Autodesk Fusion 360 part; units mm, degrees
(part 2 of 2)
sketch "スケッチ14" plane through (0, 0, 4.3) normal (0, 0, 1) x (1, 0, 0) in component "Upper_L_PROTECTIVE_ROOF_23_LP_OPENINGS_PROVISIONAL"
  line L0 (-31.4193, -16.4062) -> (-45.5193, -16.4062)
  line L1 (-45.5193, -16.4062) -> (-45.5193, -30.5062)
  line L2 (-45.5193, -30.5062) -> (-31.4193, -30.5062)
  line L3 (-31.4193, -30.5062) -> (-31.4193, -16.4062)
  line L4 (-12.3693, -18.9065) -> (-26.4693, -18.9065)
  line L5 (-26.4693, -18.9065) -> (-26.4693, -33.0065)
  line L6 (-26.4693, -33.0065) -> (-12.3693, -33.0065)
  line L7 (-12.3693, -33.0065) -> (-12.3693, -18.9065)
  line L8 (-50.4937, -51.986) -> (-64.5937, -51.986)
  line L9 (-64.5937, -51.986) -> (-64.5937, -66.086)
  line L10 (-64.5937, -66.086) -> (-50.4937, -66.086)
  line L11 (-50.4937, -66.086) -> (-50.4937, -51.986)
  line L12 (-1.074, -80.3405) -> (12.1756, -85.163)
  line L13 (12.1756, -85.163) -> (16.9981, -71.9133)
  line L14 (16.9981, -71.9133) -> (3.7485, -67.0908)
  line L15 (3.7485, -67.0908) -> (-1.074, -80.3405)
  line L16 (-12.3693, -37.9565) -> (-26.4693, -37.9565)
  line L17 (-26.4693, -37.9565) -> (-26.4693, -52.0565)
  line L18 (-26.4693, -52.0565) -> (-12.3693, -52.0565)
  line L19 (-12.3693, -52.0565) -> (-12.3693, -37.9565)
  line L20 (-88.5693, -6.556) -> (-102.6693, -6.556)
  line L21 (-102.6693, -6.556) -> (-102.6693, -20.656)
  line L22 (-102.6693, -20.656) -> (-88.5693, -20.656)
  line L23 (-88.5693, -20.656) -> (-88.5693, -6.556)
  line L24 (-31.4193, 2.6438) -> (-45.5193, 2.6438)
  line L25 (-45.5193, 2.6438) -> (-45.5193, -11.4562)
  line L26 (-45.5193, -11.4562) -> (-31.4193, -11.4562)
  line L27 (-31.4193, -11.4562) -> (-31.4193, 2.6438)
  line L28 (-50.4693, -13.906) -> (-64.5693, -13.906)
  line L29 (-64.5693, -13.906) -> (-64.5693, -28.006)
  line L30 (-64.5693, -28.006) -> (-50.4693, -28.006)
  line L31 (-50.4693, -28.006) -> (-50.4693, -13.906)
  line L32 (-50.4693, 5.144) -> (-64.5693, 5.144)
  line L33 (-64.5693, 5.144) -> (-64.5693, -8.956)
  line L34 (-64.5693, -8.956) -> (-50.4693, -8.956)
  line L35 (-50.4693, -8.956) -> (-50.4693, 5.144)
  line L36 (-31.4193, -35.4562) -> (-45.5193, -35.4562)
  line L37 (-45.5193, -35.4562) -> (-45.5193, -49.5562)
  line L38 (-45.5193, -49.5562) -> (-31.4193, -49.5562)
  line L39 (-31.4193, -49.5562) -> (-31.4193, -35.4562)
  line L40 (-50.4693, -32.956) -> (-64.5693, -32.956)
  line L41 (-64.5693, -32.956) -> (-64.5693, -47.056)
  line L42 (-64.5693, -47.056) -> (-50.4693, -47.056)
  line L43 (-50.4693, -47.056) -> (-50.4693, -32.956)
  line L44 (-69.5193, 0.4435) -> (-83.6193, 0.4435)
  line L45 (-83.6193, 0.4435) -> (-83.6193, -13.6565)
  line L46 (-83.6193, -13.6565) -> (-69.5193, -13.6565)
  line L47 (-69.5193, -13.6565) -> (-69.5193, 0.4435)
  line L48 (-88.5693, -63.706) -> (-102.6693, -63.706)
  line L49 (-102.6693, -63.706) -> (-102.6693, -77.806)
  line L50 (-102.6693, -77.806) -> (-88.5693, -77.806)
  line L51 (-88.5693, -77.806) -> (-88.5693, -63.706)
  line L52 (-12.3693, 0.1435) -> (-26.4693, 0.1435)
  line L53 (-26.4693, 0.1435) -> (-26.4693, -13.9565)
  line L54 (-26.4693, -13.9565) -> (-12.3693, -13.9565)
  line L55 (-12.3693, -13.9565) -> (-12.3693, 0.1435)
  line L56 (6.6807, -42.481) -> (-7.4193, -42.481)
  line L57 (-7.4193, -42.481) -> (-7.4193, -56.581)
  line L58 (-7.4193, -56.581) -> (6.6807, -56.581)
  line L59 (6.6807, -56.581) -> (6.6807, -42.481)
  line L60 (-69.5193, -18.6065) -> (-83.6193, -18.6065)
  line L61 (-83.6193, -18.6065) -> (-83.6193, -32.7065)
  line L62 (-83.6193, -32.7065) -> (-69.5193, -32.7065)
  line L63 (-69.5193, -32.7065) -> (-69.5193, -18.6065)
  line L64 (6.6907, -23.436) -> (-7.4093, -23.436)
  line L65 (-7.4093, -23.436) -> (-7.4093, -37.536)
  line L66 (-7.4093, -37.536) -> (6.6907, -37.536)
  line L67 (6.6907, -37.536) -> (6.6907, -23.436)
  line L68 (-88.5693, -44.656) -> (-102.6693, -44.656)
  line L69 (-102.6693, -44.656) -> (-102.6693, -58.756)
  line L70 (-102.6693, -58.756) -> (-88.5693, -58.756)
  line L71 (-88.5693, -58.756) -> (-88.5693, -44.656)
  line L72 (-88.5693, -25.606) -> (-102.6693, -25.606)
  line L73 (-102.6693, -25.606) -> (-102.6693, -39.706)
  line L74 (-102.6693, -39.706) -> (-88.5693, -39.706)
  line L75 (-88.5693, -39.706) -> (-88.5693, -25.606)
  line L76 (-41.5023, -75.8813) -> (-27.4023, -75.8813)
  line L77 (-27.4023, -75.8813) -> (-27.4023, -61.7813)
  line L78 (-27.4023, -61.7813) -> (-41.5023, -61.7813)
  line L79 (-41.5023, -61.7813) -> (-41.5023, -75.8813)
  line L80 (-69.5193, -56.7065) -> (-83.6193, -56.7065)
  line L81 (-83.6193, -56.7065) -> (-83.6193, -70.8065)
  line L82 (-83.6193, -70.8065) -> (-69.5193, -70.8065)
  line L83 (-69.5193, -70.8065) -> (-69.5193, -56.7065)
  line L84 (-69.5193, -37.6565) -> (-83.6193, -37.6565)
  line L85 (-83.6193, -37.6565) -> (-83.6193, -51.7565)
  line L86 (-83.6193, -51.7565) -> (-69.5193, -51.7565)
  line L87 (-69.5193, -51.7565) -> (-69.5193, -37.6565)
  line L88 (-21.1812, -76.4316) -> (-7.2547, -78.6373)
  line L89 (-7.2547, -78.6373) -> (-5.049, -64.7109)
  line L90 (-5.049, -64.7109) -> (-18.9754, -62.5052)
  line L91 (-18.9754, -62.5052) -> (-21.1812, -76.4316)
extrude "Twenty_three_LP_openings_14p1" cut sketch "スケッチ14" along normal blind 1.2 bodies 6 in component "Upper_L_PROTECTIVE_ROOF_23_LP_OPENINGS_PROVISIONAL"
sketch "スケッチ15" plane through (0, 0, 4.3) normal (0, 0, 1) x (1, 0, 0) in component "Upper_L_PROTECTIVE_ROOF_23_LP_OPENINGS_PROVISIONAL"
  circle A0 centre (-31.7729, -16.7598) radius 0.5
  circle A1 centre (-31.7729, -30.1527) radius 0.5
  circle A2 centre (-45.1658, -16.7598) radius 0.5
  circle A3 centre (-45.1658, -30.1527) radius 0.5
  circle A4 centre (-12.7229, -19.2601) radius 0.5
  circle A5 centre (-12.7229, -32.6529) radius 0.5
  circle A6 centre (-26.1158, -19.2601) radius 0.5
  circle A7 centre (-26.1158, -32.6529) radius 0.5
  circle A8 centre (-50.8472, -52.3396) radius 0.5
  circle A9 centre (-50.8472, -65.7324) radius 0.5
  circle A10 centre (-64.2401, -52.3396) radius 0.5
  circle A11 centre (-64.2401, -65.7324) radius 0.5
  circle A12 centre (-0.6209, -80.1292) radius 0.5
  circle A13 centre (3.9598, -67.544) radius 0.5
  circle A14 centre (11.9643, -84.7098) radius 0.5
  circle A15 centre (16.545, -72.1246) radius 0.5
  circle A16 centre (-12.7229, -38.3101) radius 0.5
  circle A17 centre (-12.7229, -51.7029) radius 0.5
  circle A18 centre (-26.1158, -38.3101) radius 0.5
  circle A19 centre (-26.1158, -51.7029) radius 0.5
  circle A20 centre (-88.9229, -6.9096) radius 0.5
  circle A21 centre (-88.9229, -20.3024) radius 0.5
  circle A22 centre (-102.3158, -6.9096) radius 0.5
  circle A23 centre (-102.3158, -20.3024) radius 0.5
  circle A24 centre (-31.7729, 2.2902) radius 0.5
  circle A25 centre (-31.7729, -11.1027) radius 0.5
  circle A26 centre (-45.1658, 2.2902) radius 0.5
  circle A27 centre (-45.1658, -11.1027) radius 0.5
  circle A28 centre (-50.8229, -14.2596) radius 0.5
  circle A29 centre (-50.8229, -27.6524) radius 0.5
  circle A30 centre (-64.2158, -14.2596) radius 0.5
  circle A31 centre (-64.2158, -27.6524) radius 0.5
  circle A32 centre (-50.8229, 4.7904) radius 0.5
  circle A33 centre (-50.8229, -8.6024) radius 0.5
  circle A34 centre (-64.2158, 4.7904) radius 0.5
  circle A35 centre (-64.2158, -8.6024) radius 0.5
  circle A36 centre (-31.7729, -35.8098) radius 0.5
  circle A37 centre (-31.7729, -49.2027) radius 0.5
  circle A38 centre (-45.1658, -35.8098) radius 0.5
  circle A39 centre (-45.1658, -49.2027) radius 0.5
  circle A40 centre (-50.8229, -33.3096) radius 0.5
  circle A41 centre (-50.8229, -46.7024) radius 0.5
  circle A42 centre (-64.2158, -33.3096) radius 0.5
  circle A43 centre (-64.2158, -46.7024) radius 0.5
  circle A44 centre (-69.8729, 0.0899) radius 0.5
  circle A45 centre (-69.8729, -13.3029) radius 0.5
  circle A46 centre (-83.2658, 0.0899) radius 0.5
  circle A47 centre (-83.2658, -13.3029) radius 0.5
  circle A48 centre (-88.9229, -64.0596) radius 0.5
  circle A49 centre (-88.9229, -77.4524) radius 0.5
  circle A50 centre (-102.3158, -64.0596) radius 0.5
  circle A51 centre (-102.3158, -77.4524) radius 0.5
  circle A52 centre (-12.7229, -0.2101) radius 0.5
  circle A53 centre (-12.7229, -13.6029) radius 0.5
  circle A54 centre (-26.1158, -0.2101) radius 0.5
  circle A55 centre (-26.1158, -13.6029) radius 0.5
  circle A56 centre (6.3271, -42.8346) radius 0.5
  circle A57 centre (6.3271, -56.2274) radius 0.5
  circle A58 centre (-7.0658, -42.8346) radius 0.5
  circle A59 centre (-7.0658, -56.2274) radius 0.5
  circle A60 centre (-69.8729, -18.9601) radius 0.5
  circle A61 centre (-69.8729, -32.3529) radius 0.5
  circle A62 centre (-83.2658, -18.9601) radius 0.5
  circle A63 centre (-83.2658, -32.3529) radius 0.5
  circle A64 centre (6.3371, -23.7896) radius 0.5
  circle A65 centre (6.3371, -37.1824) radius 0.5
  circle A66 centre (-7.0558, -23.7896) radius 0.5
  circle A67 centre (-7.0558, -37.1824) radius 0.5
  circle A68 centre (-88.9229, -45.0096) radius 0.5
  circle A69 centre (-88.9229, -58.4024) radius 0.5
  circle A70 centre (-102.3158, -45.0096) radius 0.5
  circle A71 centre (-102.3158, -58.4024) radius 0.5
  circle A72 centre (-88.9229, -25.9596) radius 0.5
  circle A73 centre (-88.9229, -39.3524) radius 0.5
  circle A74 centre (-102.3158, -25.9596) radius 0.5
  circle A75 centre (-102.3158, -39.3524) radius 0.5
  circle A76 centre (-41.1488, -75.5277) radius 0.5
  circle A77 centre (-41.1488, -62.1348) radius 0.5
  circle A78 centre (-27.7559, -75.5277) radius 0.5
  circle A79 centre (-27.7559, -62.1348) radius 0.5
  circle A80 centre (-69.8729, -57.0601) radius 0.5
  circle A81 centre (-69.8729, -70.4529) radius 0.5
  circle A82 centre (-83.2658, -57.0601) radius 0.5
  circle A83 centre (-83.2658, -70.4529) radius 0.5
  circle A84 centre (-69.8729, -38.0101) radius 0.5
  circle A85 centre (-69.8729, -51.4029) radius 0.5
  circle A86 centre (-83.2658, -38.0101) radius 0.5
  circle A87 centre (-83.2658, -51.4029) radius 0.5
  circle A88 centre (-20.7766, -76.1377) radius 0.5
  circle A89 centre (-18.6815, -62.9097) radius 0.5
  circle A90 centre (-7.5486, -78.2328) radius 0.5
  circle A91 centre (-5.4535, -65.0048) radius 0.5
extrude "Ninety_two_corner_reliefs_R0p5" cut sketch "スケッチ15" along normal blind 1.2 bodies 6 in component "Upper_L_PROTECTIVE_ROOF_23_LP_OPENINGS_PROVISIONAL"
sketch "スケッチ16" plane through (0, 0, 4.3) normal (0, 0, 1) x (1, 0, 0) in component "Upper_L_PROTECTIVE_ROOF_23_LP_OPENINGS_PROVISIONAL"
  line L0 (-9.5, -21.1) -> (9.5, -21.1)
  line L1 (9.5, -21.1) -> (9.5, 2.6)
  line L2 (9.5, 2.6) -> (-9.5, 2.6)
  line L3 (-9.5, 2.6) -> (-9.5, -21.1)
extrude "Controller_opening_for_separate_nonmetal_cover" cut sketch "スケッチ16" along normal blind 1.2 bodies 6 in component "Upper_L_PROTECTIVE_ROOF_23_LP_OPENINGS_PROVISIONAL"
combine "Join_perforated_roof_to_perimeter_only" operation add target body 2 tool bodies 6 in component "Upper_L_PROTECTIVE_ROOF_23_LP_OPENINGS_PROVISIONAL"
ref_plane "作業平面1" through (0, 0, 3) normal (0, 0, 1) x (1, 0, 0) in component "MCU_NONMETAL_COVER_CONCEPT_RETENTION_PENDING"
sketch "スケッチ1 (6)" plane through (0, 0, 3) normal (0, 0, 1) x (1, 0, 0) in component "MCU_NONMETAL_COVER_CONCEPT_RETENTION_PENDING"
  line L0 (-9.9, -20.95) -> (9.9, -20.95)
  line L1 (9.9, -20.95) -> (9.9, 3)
  line L2 (9.9, 3) -> (-9.9, 3)
  line L3 (-9.9, 3) -> (-9.9, -20.95)
extrude "押し出し1''" add sketch "スケッチ1 (6)" along normal blind 1.2 separate body makes body 7 in component "MCU_NONMETAL_COVER_CONCEPT_RETENTION_PENDING"
ref_plane "作業平面2" through (0, 0, 0) normal (0, 0, 1) x (1, 0, 0) in component "MCU_NONMETAL_COVER_CONCEPT_RETENTION_PENDING"
sketch "スケッチ2 (4)" plane through (0, 0, 0) normal (0, 0, 1) x (1, 0, 0) in component "MCU_NONMETAL_COVER_CONCEPT_RETENTION_PENDING"
  line L0 (-9.9, -20.95) -> (-9.1, -20.95)
  line L1 (-9.1, -20.95) -> (-9.1, 3)
  line L2 (-9.1, 3) -> (-9.9, 3)
  line L3 (-9.9, 3) -> (-9.9, -20.95)
extrude "押し出し2" add sketch "スケッチ2 (4)" along normal blind 3 separate body makes body 8 in component "MCU_NONMETAL_COVER_CONCEPT_RETENTION_PENDING"
ref_plane "作業平面3" through (0, 0, 0) normal (0, 0, 1) x (1, 0, 0) in component "MCU_NONMETAL_COVER_CONCEPT_RETENTION_PENDING"
sketch "スケッチ3 (3)" plane through (0, 0, 0) normal (0, 0, 1) x (1, 0, 0) in component "MCU_NONMETAL_COVER_CONCEPT_RETENTION_PENDING"
  line L0 (9.1, -20.95) -> (9.9, -20.95)
  line L1 (9.9, -20.95) -> (9.9, 3)
  line L2 (9.9, 3) -> (9.1, 3)
  line L3 (9.1, 3) -> (9.1, -20.95)
extrude "押し出し3" add sketch "スケッチ3 (3)" along normal blind 3 separate body makes body 9 in component "MCU_NONMETAL_COVER_CONCEPT_RETENTION_PENDING"
ref_plane "作業平面4" through (0, 0, 0) normal (0, 0, 1) x (1, 0, 0) in component "MCU_NONMETAL_COVER_CONCEPT_RETENTION_PENDING"
sketch "スケッチ4 (3)" plane through (0, 0, 0) normal (0, 0, 1) x (1, 0, 0) in component "MCU_NONMETAL_COVER_CONCEPT_RETENTION_PENDING"
  line L0 (-9.9, 2.2) -> (9.9, 2.2)
  line L1 (9.9, 2.2) -> (9.9, 3)
  line L2 (9.9, 3) -> (-9.9, 3)
  line L3 (-9.9, 3) -> (-9.9, 2.2)
extrude "押し出し4" add sketch "スケッチ4 (3)" along normal blind 3 separate body makes body 10 in component "MCU_NONMETAL_COVER_CONCEPT_RETENTION_PENDING"
ref_plane "作業平面5" through (0, 0, 0.7) normal (0, 0, 1) x (1, 0, 0) in component "MCU_NONMETAL_COVER_CONCEPT_RETENTION_PENDING"
sketch "スケッチ5 (3)" plane through (0, 0, 0.7) normal (0, 0, 1) x (1, 0, 0) in component "MCU_NONMETAL_COVER_CONCEPT_RETENTION_PENDING"
  line L0 (-9.9, -20.95) -> (9.9, -20.95)
  line L1 (9.9, -20.95) -> (9.9, -20.15)
  line L2 (9.9, -20.15) -> (-9.9, -20.15)
  line L3 (-9.9, -20.15) -> (-9.9, -20.95)
extrude "押し出し5" add sketch "スケッチ5 (3)" along normal blind 2.3 separate body makes body 11 in component "MCU_NONMETAL_COVER_CONCEPT_RETENTION_PENDING"
combine "Join_nonmetal_cover_roof_and_skirts" operation add target body 7 tool bodies 8 9 10 11 in component "MCU_NONMETAL_COVER_CONCEPT_RETENTION_PENDING"
sketch "スケッチ6 (3)" plane through (0, 0, 0) normal (0, 0, 1) x (1, 0, 0) in component "MCU_NONMETAL_COVER_CONCEPT_RETENTION_PENDING"
  line L0 (-6, 1.5) -> (6, 1.5)
  line L1 (6, 1.5) -> (6, 4)
  line L2 (6, 4) -> (-6, 4)
  line L3 (-6, 4) -> (-6, 1.5)
extrude "Open_front_for_USB_cable" cut sketch "スケッチ6 (3)" along normal blind 3 bodies 7 in component "MCU_NONMETAL_COVER_CONCEPT_RETENTION_PENDING"
ref_plane "作業平面1" through (0, 0, 1.6) normal (0, 0, 1) x (1, 0, 0) in component "SWITCH_MAX_HOUSING_14mm_ENVELOPES_NOT_LATCHES"
sketch "スケッチ1 (7)" plane through (0, 0, 1.6) normal (0, 0, 1) x (1, 0, 0) in component "SWITCH_MAX_HOUSING_14mm_ENVELOPES_NOT_LATCHES"
  line L0 (-31.4693, -16.4562) -> (-45.4693, -16.4562)
  line L1 (-45.4693, -16.4562) -> (-45.4693, -30.4562)
  line L2 (-45.4693, -30.4562) -> (-31.4693, -30.4562)
  line L3 (-31.4693, -30.4562) -> (-31.4693, -16.4562)
  line L4 (-12.4193, -18.9565) -> (-26.4193, -18.9565)
  line L5 (-26.4193, -18.9565) -> (-26.4193, -32.9565)
  line L6 (-26.4193, -32.9565) -> (-12.4193, -32.9565)
  line L7 (-12.4193, -32.9565) -> (-12.4193, -18.9565)
  line L8 (-50.5437, -52.036) -> (-64.5437, -52.036)
  line L9 (-64.5437, -52.036) -> (-64.5437, -66.036)
  line L10 (-64.5437, -66.036) -> (-50.5437, -66.036)
  line L11 (-50.5437, -66.036) -> (-50.5437, -52.036)
  line L12 (-1.0099, -80.3106) -> (12.1458, -85.0989)
  line L13 (12.1458, -85.0989) -> (16.934, -71.9432)
  line L14 (16.934, -71.9432) -> (3.7783, -67.1549)
  line L15 (3.7783, -67.1549) -> (-1.0099, -80.3106)
  line L16 (-12.4193, -38.0065) -> (-26.4193, -38.0065)
  line L17 (-26.4193, -38.0065) -> (-26.4193, -52.0065)
  line L18 (-26.4193, -52.0065) -> (-12.4193, -52.0065)
  line L19 (-12.4193, -52.0065) -> (-12.4193, -38.0065)
  line L20 (-88.6193, -6.606) -> (-102.6193, -6.606)
  line L21 (-102.6193, -6.606) -> (-102.6193, -20.606)
  line L22 (-102.6193, -20.606) -> (-88.6193, -20.606)
  line L23 (-88.6193, -20.606) -> (-88.6193, -6.606)
  line L24 (-31.4693, 2.5938) -> (-45.4693, 2.5938)
  line L25 (-45.4693, 2.5938) -> (-45.4693, -11.4062)
  line L26 (-45.4693, -11.4062) -> (-31.4693, -11.4062)
  line L27 (-31.4693, -11.4062) -> (-31.4693, 2.5938)
  line L28 (-50.5193, -13.956) -> (-64.5193, -13.956)
  line L29 (-64.5193, -13.956) -> (-64.5193, -27.956)
  line L30 (-64.5193, -27.956) -> (-50.5193, -27.956)
  line L31 (-50.5193, -27.956) -> (-50.5193, -13.956)
  line L32 (-50.5193, 5.094) -> (-64.5193, 5.094)
  line L33 (-64.5193, 5.094) -> (-64.5193, -8.906)
  line L34 (-64.5193, -8.906) -> (-50.5193, -8.906)
  line L35 (-50.5193, -8.906) -> (-50.5193, 5.094)
  line L36 (-31.4693, -35.5062) -> (-45.4693, -35.5062)
  line L37 (-45.4693, -35.5062) -> (-45.4693, -49.5062)
  line L38 (-45.4693, -49.5062) -> (-31.4693, -49.5062)
  line L39 (-31.4693, -49.5062) -> (-31.4693, -35.5062)
  line L40 (-50.5193, -33.006) -> (-64.5193, -33.006)
  line L41 (-64.5193, -33.006) -> (-64.5193, -47.006)
  line L42 (-64.5193, -47.006) -> (-50.5193, -47.006)
  line L43 (-50.5193, -47.006) -> (-50.5193, -33.006)
  line L44 (-69.5693, 0.3935) -> (-83.5693, 0.3935)
  line L45 (-83.5693, 0.3935) -> (-83.5693, -13.6065)
  line L46 (-83.5693, -13.6065) -> (-69.5693, -13.6065)
  line L47 (-69.5693, -13.6065) -> (-69.5693, 0.3935)
  line L48 (-88.6193, -63.756) -> (-102.6193, -63.756)
  line L49 (-102.6193, -63.756) -> (-102.6193, -77.756)
  line L50 (-102.6193, -77.756) -> (-88.6193, -77.756)
  line L51 (-88.6193, -77.756) -> (-88.6193, -63.756)
  line L52 (-12.4193, 0.0935) -> (-26.4193, 0.0935)
  line L53 (-26.4193, 0.0935) -> (-26.4193, -13.9065)
  line L54 (-26.4193, -13.9065) -> (-12.4193, -13.9065)
  line L55 (-12.4193, -13.9065) -> (-12.4193, 0.0935)
  line L56 (6.6307, -42.531) -> (-7.3693, -42.531)
  line L57 (-7.3693, -42.531) -> (-7.3693, -56.531)
  line L58 (-7.3693, -56.531) -> (6.6307, -56.531)
  line L59 (6.6307, -56.531) -> (6.6307, -42.531)
  line L60 (-69.5693, -18.6565) -> (-83.5693, -18.6565)
  line L61 (-83.5693, -18.6565) -> (-83.5693, -32.6565)
  line L62 (-83.5693, -32.6565) -> (-69.5693, -32.6565)
  line L63 (-69.5693, -32.6565) -> (-69.5693, -18.6565)
  line L64 (6.6407, -23.486) -> (-7.3593, -23.486)
  line L65 (-7.3593, -23.486) -> (-7.3593, -37.486)
  line L66 (-7.3593, -37.486) -> (6.6407, -37.486)
  line L67 (6.6407, -37.486) -> (6.6407, -23.486)
  line L68 (-88.6193, -44.706) -> (-102.6193, -44.706)
  line L69 (-102.6193, -44.706) -> (-102.6193, -58.706)
  line L70 (-102.6193, -58.706) -> (-88.6193, -58.706)
  line L71 (-88.6193, -58.706) -> (-88.6193, -44.706)
  line L72 (-88.6193, -25.656) -> (-102.6193, -25.656)
  line L73 (-102.6193, -25.656) -> (-102.6193, -39.656)
  line L74 (-102.6193, -39.656) -> (-88.6193, -39.656)
  line L75 (-88.6193, -39.656) -> (-88.6193, -25.656)
  line L76 (-41.4523, -75.8313) -> (-27.4523, -75.8313)
  line L77 (-27.4523, -75.8313) -> (-27.4523, -61.8313)
  line L78 (-27.4523, -61.8313) -> (-41.4523, -61.8313)
  line L79 (-41.4523, -61.8313) -> (-41.4523, -75.8313)
  line L80 (-69.5693, -56.7565) -> (-83.5693, -56.7565)
  line L81 (-83.5693, -56.7565) -> (-83.5693, -70.7565)
  line L82 (-83.5693, -70.7565) -> (-69.5693, -70.7565)
  line L83 (-69.5693, -70.7565) -> (-69.5693, -56.7565)
  line L84 (-69.5693, -37.7065) -> (-83.5693, -37.7065)
  line L85 (-83.5693, -37.7065) -> (-83.5693, -51.7065)
  line L86 (-83.5693, -51.7065) -> (-69.5693, -51.7065)
  line L87 (-69.5693, -51.7065) -> (-69.5693, -37.7065)
  line L88 (-21.1239, -76.39) -> (-7.2963, -78.5801)
  line L89 (-7.2963, -78.5801) -> (-5.1062, -64.7525)
  line L90 (-5.1062, -64.7525) -> (-18.9339, -62.5624)
  line L91 (-18.9339, -62.5624) -> (-21.1239, -76.39)
extrude "押し出し1'''" add sketch "スケッチ1 (7)" along normal blind 2.9 separate body makes body 12 at (-74.236, -47.0398, 1.6) makes body 13 at (-36.7857, -66.4979, 1.6) makes body 14 at (-97.9527, -49.3727, 1.6) makes body 15 at (-78.9027, -23.3232, 1.6) makes body 16 at (-17.086, -9.2398, 1.6) makes body 17 at (-36.136, -25.7896, 1.6) makes body 18 at (-59.8527, -37.6727, 1.6) makes body 19 at (-55.186, 0.4273, 1.6) makes body 20 at (-36.136, -6.7396, 1.6) makes body 21 at (-21.7527, -42.6732, 1.6) makes body 22 at (-59.877, -56.7027, 1.6) makes body 23 at (-21.7527, -23.6232, 1.6) makes body 24 at (9.3566, -79.1176, 1.6) makes body 25 at (-97.9527, -11.2727, 1.6) makes body 26 at (-55.186, -18.6227, 1.6) makes body 27 at (-36.136, -44.8396, 1.6) makes body 28 at (-74.236, -8.9398, 1.6) makes body 29 at (-97.9527, -68.4227, 1.6) makes body 30 at (1.964, -51.8643, 1.6) makes body 31 at (-2.6927, -32.8193, 1.6) makes body 32 at (-97.9527, -30.3227, 1.6) makes body 33 at (-78.9027, -61.4232, 1.6) makes body 34 at (-15.7847, -72.5108, 1.6) in component "SWITCH_MAX_HOUSING_14mm_ENVELOPES_NOT_LATCHES"
sketch "スケッチ1 (8)" plane through (0, 0, 0) normal (0, 0, 1) x (1, 0, 0) in component "USB_CABLE_ACCESS_ASSUMED_NOT_A_PART"
  line L0 (-6, 0) -> (6, 0)
  line L1 (6, 0) -> (6, 18)
  line L2 (6, 18) -> (-6, 18)
  line L3 (-6, 18) -> (-6, 0)
extrude "押し出し1''''" add sketch "スケッチ1 (8)" along normal blind 6 separate body makes body 35 in component "USB_CABLE_ACCESS_ASSUMED_NOT_A_PART"
component "Lower_L_FROM_PCB_OUTLINE_PROVISIONAL" placed x (1, 0, 0) y (0, 1, 0) z (0, 0, 1) at (0, 0, -11.5)
component "Upper_L_PROTECTIVE_ROOF_23_LP_OPENINGS_PROVISIONAL" placed x (1, 0, 0) y (0, 1, 0) z (0, 0, 1) at (0, 0, -1)
component "PCB_L_v2_OUTLINE_REFERENCE_ACTUAL_REVISION_UNKNOWN" placed x (1, 0, 0) y (0, 1, 0) z (0, 0, 1) at (0, 0, 0)
component "Battery_L_ALLOWANCE_32x22x5p5_NOT_CELL" placed x (1, 0, 0) y (0, 1, 0) z (0, 0, 1) at (-66, -51, -9)
component "XIAO_KEY_SIDE_ENVELOPE_FROM_OLD_SINGLE_PART_UNVERIFIED" placed x (1, 0, 0) y (0, 1, 0) z (0, 0, 1) at (-8.89, -20.955, 1.6)
component "MCU_NONMETAL_COVER_CONCEPT_RETENTION_PENDING" placed x (1, 0, 0) y (0, 1, 0) z (0, 0, 1) at (0, 0, 4.5)
component "SWITCH_MAX_HOUSING_14mm_ENVELOPES_NOT_LATCHES" placed x (1, 0, 0) y (0, 1, 0) z (0, 0, 1) at (0, 0, 0)
component "USB_CABLE_ACCESS_ASSUMED_NOT_A_PART" placed x (1, 0, 0) y (0, 1, 0) z (0, 0, 1) at (0, 0, 1)
equation "outside_offset = 4 mm" comment "Provisional study, actual hardware/fit not verified"
equation "PCB_side_clearance = 1 mm" comment "Provisional study, actual hardware/fit not verified"
equation "floor_thickness = 2 mm" comment "Provisional study, actual hardware/fit not verified"
equation "lower_wall_height = 8.5 mm" comment "Provisional study, actual hardware/fit not verified"
equation "upper_frame_height = 5.5 mm" comment "Provisional study, actual hardware/fit not verified"
equation "stand_depth = 3.7 mm" comment "Provisional study, actual hardware/fit not verified"
equation "stand_residual = 2 mm" comment "Provisional study, actual hardware/fit not verified"
equation "support_height = 3.3 mm" comment "Provisional study, actual hardware/fit not verified"
equation "M2_clearance = 2.2 mm" comment "Provisional study, actual hardware/fit not verified"
equation "M2_tap_pilot = 1.6 mm" comment "Provisional study, actual hardware/fit not verified"
equation "M2_pilot_depth = 4.5 mm" comment "Provisional study, actual hardware/fit not verified"
equation "boss_diameter = 6 mm" comment "Provisional study, actual hardware/fit not verified"
equation "d13 = outside_offset"
equation "d14 = floor_thickness"
equation "d16 = floor_thickness"
equation "d18 = outside_offset"
equation "d19 = PCB_side_clearance"
equation "d20 = lower_wall_height"
equation "d22 = stand_depth + stand_residual - floor_thickness"
equation "d24 = stand_depth + stand_residual - floor_thickness"
equation "d26 = stand_depth"
equation "d28 = stand_depth"
equation "d32 = support_height"
equation "d34 = support_height"
equation "d36 = support_height"
equation "d38 = support_height"
equation "d40 = outside_offset"
equation "d41 = PCB_side_clearance"
equation "d42 = upper_frame_height"
equation "d44 = floor_thickness + lower_wall_height"
equation "d46 = upper_frame_height"
equation "d48 = floor_thickness + lower_wall_height"
equation "d50 = M2_pilot_depth"
equation "head_seat_depth = 2.2 mm" comment "Provisional socket head recess"
equation "d75 = head_seat_depth"
equation "roof_top_global = 4.5 mm" comment "Provisional upper roof; switch seating/physical fit unverified"
equation "roof_lip_thickness = 1.2 mm" comment "Provisional upper roof; switch seating/physical fit unverified"
equation "roof_outline_offset = 1.8 mm" comment "Provisional upper roof; switch seating/physical fit unverified"
equation "d92 = roof_top_global - roof_lip_thickness + 1 mm"
equation "d94 = roof_outline_offset"
equation "d95 = roof_lip_thickness"
equation "d97 = roof_lip_thickness"
equation "d99 = roof_lip_thickness"
equation "d101 = roof_lip_thickness"
